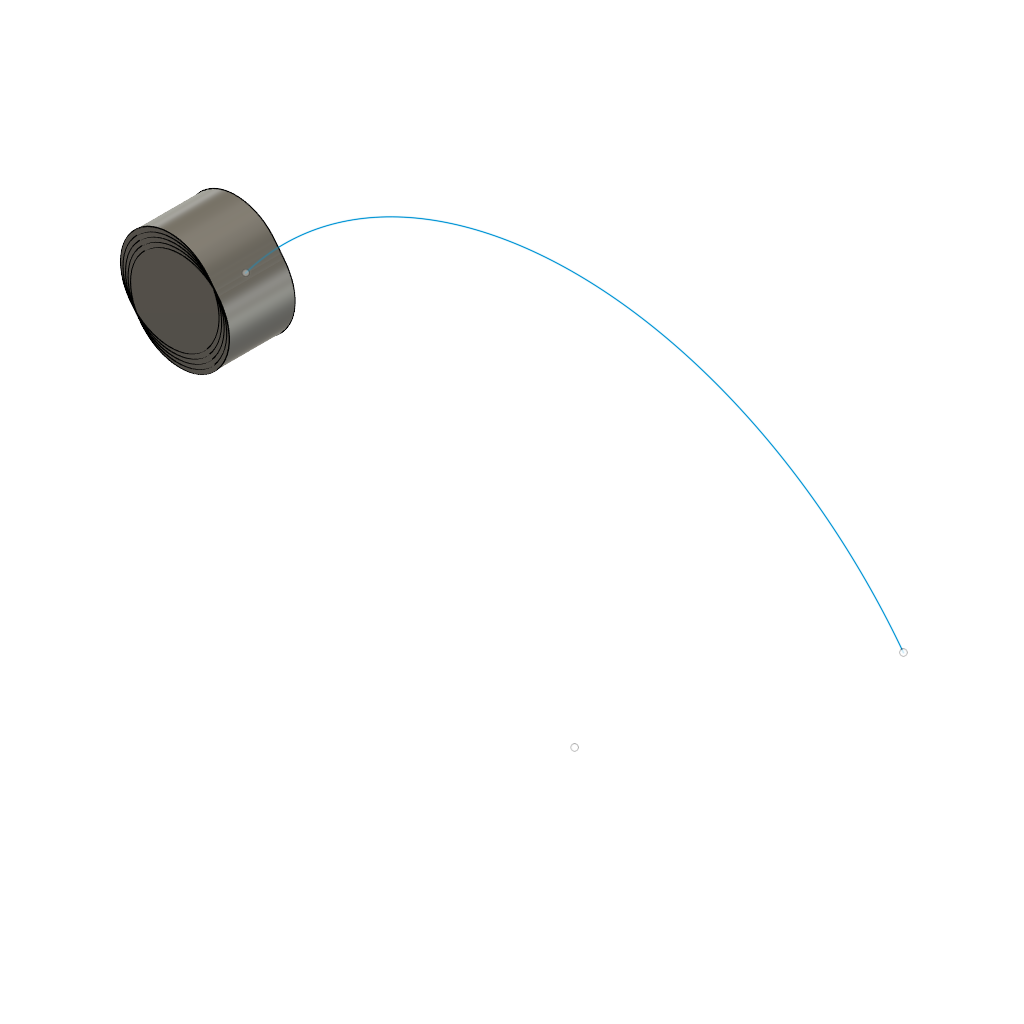
pat_path (Autodesk Fusion 360 design; units mm, degrees)
part number: 2026-11-13-14-44-11-954
Autodesk Fusion 360 part; units mm, degrees
sketch "Sketch1" plane through (0, 0, 0) normal (0, 0, 1) x (1, 0, 0)
  circle A0 centre (0, 0) radius 3
extrude "Extrude1" add sketch "Sketch1" along normal blind 4 makes body 1
sketch "Sketch2" plane through (0, 0, 0) normal (0, 0, 1) x (1, 0, 0)
  arc A0 (40, 0) -> (0, 0) centre (20, -15) ccw
pattern_path "PathPattern1" count 5 spacing 0.25 from (40, 0, 0) path "Sketch2" along A0 of bodies 1 makes body 2 at (2.8453, 0.0497, 2.6667) makes body 3 at (2.6923, 0.2474, 2.6667) makes body 4 at (2.5373, 0.4436, 2.6667) makes body 5 at (2.3804, 0.6383, 2.6667)
